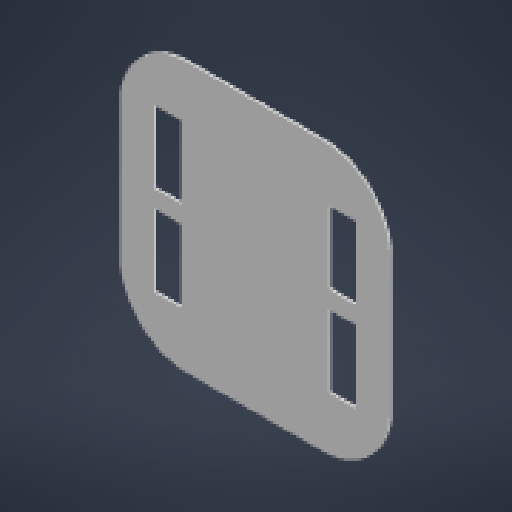
# Autodesk Inventor part: plate
Saved by Autodesk Inventor 2025.2 (Build 292293000, 293)
## iProperties
Created: 2024-12-25
Part Number: plate
Material: Generic
Document SubType Name: Modeling
Designer: user
Density: 1 g/cm^3
Appearance: Default
Author: user
Autodesk Inventor part; units mm, degrees
ref_plane "YZ Plane" through (0, 0, 0) normal (1, 0, 0) x (0, 1, 0)
ref_plane "XZ Plane" through (0, 0, 0) normal (0, 1, 0) x (-1, 0, 0)
ref_plane "XY Plane" through (0, 0, 0) normal (0, 0, 1) x (1, 0, 0)
sketch "Sketch1" plane through (0, 0, 0) normal (0, 0, 1) x (1, 0, 0)
  circle A0 centre (0, 0) radius 300
  line L0 (150, 300) -> (-150, 300)
  line L1 (-300, 150) -> (-300, -150)
  line L2 (-150, -300) -> (150, -300)
  line L3 (300, -150) -> (300, 150)
  line L4 (300, 300) -> (-300, -300) construction
  line L5 (-300, 300) -> (300, -300) construction
  arc A1 (300, 150) -> (150, 300) centre (150, 150) ccw
  arc A2 (-150, 300) -> (-300, 150) centre (-150, 150) ccw
  arc A3 (-300, -150) -> (-150, -300) centre (-150, -150) ccw
  arc A4 (150, -300) -> (300, -150) centre (150, -150) ccw
  point P0 (300, 0)
  point P1 (0, -300)
  point P2 (-300, 0)
  point P3 (0, 300)
  dimension "d0" = 600
  dimension "d8" = 600
  dimension "d9" = 150
  constraints: 12 end point, 8 point on circle, 8 point on line, 8 tangent, 5 centre point, 3 equal radius, 2 midpoint, 2 parallel, 1 coincident, 1 horizontal, 1 perpendicular
  measures "d0" diameter of A0
  measures "d8" distance of L4.end L5.start
  measures "d9" radius of A1
extrude "Extrusion1" add sketch "Sketch1" along normal blind 5
sketch "Sketch2" plane through (0, 0, 0) normal (0, 0, -1) x (-1, 0, 0)
  line L0 (225, -179.8745) -> (165, -179.8745)
  line L1 (165, -179.8745) -> (165, -19.8745)
  line L2 (165, -19.8745) -> (225, -19.8745)
  line L3 (225, -19.8745) -> (225, -179.8745)
  circle A0 centre (0, 0) radius 300 construction
  line L4 (300, 0) -> (300, -300) construction
  line L5 (0, -300) -> (300, -300) construction
  line L6 (0, 0) -> (0, -223.3947) construction
  line L7 (0, 0) -> (300, 0) construction
  line L8 (-225, -179.8745) -> (-165, -179.8745)
  line L9 (-165, -179.8745) -> (-165, -19.8745)
  line L10 (-165, -19.8745) -> (-225, -19.8745)
  line L11 (-225, -19.8745) -> (-225, -179.8745)
  line L12 (225, 179.8745) -> (165, 179.8745)
  line L13 (165, 179.8745) -> (165, 19.8745)
  line L14 (165, 19.8745) -> (225, 19.8745)
  line L15 (225, 19.8745) -> (225, 179.8745)
  line L16 (-165, 179.8745) -> (-165, 19.8745)
  line L17 (-225, 179.8745) -> (-165, 179.8745)
  line L18 (-225, 19.8745) -> (-225, 179.8745)
  line L19 (-165, 19.8745) -> (-225, 19.8745)
  dimension "d3" = 60
  dimension "d4" = 160
  dimension "d5" = 75
  constraints: 40 end point, 12 symmetric about line, 3 horizontal, 2 parallel, 2 point on circle, 2 vertical, 1 perpendicular, 1 tangent
  measures "d3" distance of L1.end L2.end
  measures "d4" distance of L0.end L1.end
  measures "d5" distance between parallel lines of L4 L3
extrude "Extrusion2" cut sketch "Sketch2" against normal through all
body "Solid1"
